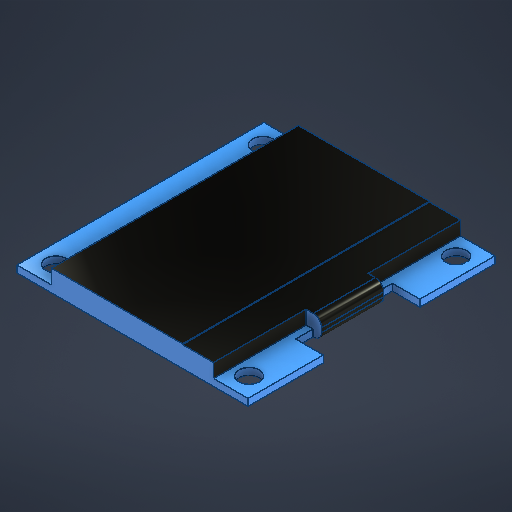
# Autodesk Inventor part: 1.3in OLED
Saved by Autodesk Inventor 2026.2 (Build 302298010, 298A)
## iProperties
Created: 2026-09-25
Part Number: 1.3in OLED
Material: 열가소성 수지
Document SubType Name: Modeling
Designer: work
Density: 1.28 g/cm^3
Appearance: 시안색
Author: work
Autodesk Inventor part; units mm, degrees
ref_plane "YZ Plane" through (0, 0, 0) normal (1, 0, 0) x (0, 1, 0)
ref_plane "XZ Plane" through (0, 0, 0) normal (0, 1, 0) x (-1, 0, 0)
ref_plane "XY Plane" through (0, 0, 0) normal (0, 0, 1) x (1, 0, 0)
sketch "스케치1" plane through (0, 0, 0) normal (0, 1, 0) x (-1, 0, 0)
  line L0 (0, 0) -> (33.5, 0)
  line L1 (33.5, 0) -> (33.5, -35.8)
  line L2 (33.5, -35.8) -> (0, -35.8)
  line L3 (0, -35.8) -> (0, 0)
  line L4 (0, -10.9) -> (4, -10.9)
  line L5 (4, -10.9) -> (4, -24.9)
  line L6 (4, -24.9) -> (0, -24.9)
  line L7 (0, -24.9) -> (0, -10.9)
  line L8 (2.75, -2.9) -> (30.75, -2.9) construction
  line L9 (30.75, -2.9) -> (30.75, -32.9) construction
  line L10 (30.75, -32.9) -> (2.75, -32.9) construction
  line L11 (2.75, -32.9) -> (2.75, -2.9) construction
  circle A0 centre (2.75, -2.9) radius 1.5
  circle A1 centre (30.75, -2.9) radius 1.5
  circle A2 centre (30.75, -32.9) radius 1.5
  circle A3 centre (2.75, -32.9) radius 1.5
  point P0 (0, -17.9)
  point P1 (16.75, -32.9)
  point P2 (16.75, -35.8)
  point P3 (33.5, -17.9)
  point P4 (30.75, -17.9)
  dimension "d0" = 33.5
  dimension "d1" = 35.8
  dimension "d2" = 4
  dimension "d3" = 14
  dimension "d4" = 28
  dimension "d5" = 30
  dimension "d6" = 3
  dimension "d7" = 3
  dimension "d8" = 3
  dimension "d9" = 3
  constraints: 24 end point, 6 midpoint, 6 parallel, 4 centre point, 4 coincident, 3 horizontal, 3 perpendicular, 1 horizontal alignment, 1 vertical alignment
  measures "d0" distance of L1.end L2.end
  measures "d1" distance of L0.end L1.end
  measures "d2" distance of L5.end L6.end
  measures "d3" distance of L4.end L5.end
  measures "d4" distance of L9.end L10.end
  measures "d5" distance of L8.end L9.end
  measures "d6" diameter of A0
  measures "d7" diameter of A1
  measures "d8" diameter of A2
  measures "d9" diameter of A3
extrude "돌출1" add sketch "스케치1" along normal blind 1 contours L0 L1 L2 L3 L6 L5 L4
sketch "스케치2" plane through (0, 1, 0) normal (0, 1, 0) x (1, 0, 0)
  line L0 (-28.5, 35.8) -> (-5, 35.8)
  line L1 (-5, 35.8) -> (-5, 0)
  line L2 (-5, 0) -> (-28.5, 0)
  line L3 (-28.5, 0) -> (-28.5, 35.8)
  line L4 (0, 35.8) -> (-33.5, 35.8) projected
  line L5 (0, 24.9) -> (0, 35.8) projected
  line L6 (-33.5, 35.8) -> (-33.5, 0) projected
  line L7 (-5, 22.4) -> (-2.736, 22.4)
  line L8 (-2.736, 22.4) -> (-2.736, 13.4)
  line L9 (-2.736, 13.4) -> (-5, 13.4)
  line L10 (-5, 13.4) -> (-5, 22.4)
  point P0 (0, 0)
  point P1 (-5, 17.9)
  dimension "d12" = 5
  dimension "d13" = 5
  dimension "d14" = 9
  constraints: 16 end point, 4 parallel, 2 horizontal, 2 midpoint, 2 perpendicular, 2 point on line
  measures "d12" distance between parallel lines of L5 L1
  measures "d13" distance between parallel lines of L6 L3
  measures "d14" distance of L7.end L8.end
extrude "돌출2" add sketch "스케치2" along normal blind 2
extrude "돌출3" add sketch "스케치2" against normal up to surface (1 mm away) contours L7 L8 L9 L1
fillet "모깎기1" radius 1.2 1 edges at (-2.736, 3, -17.9)
sketch "스케치3" plane through (0, 3, 0) normal (0, 1, 0) x (1, 0, 0)
  line L0 (-33.5, 0) -> (-28.5, 0) projected
  line L1 (0, 35.8) -> (-33.5, 35.8) projected
  line L2 (-28.5, 0) -> (-9.5, 0)
  line L3 (-9.5, 0) -> (-9.5, 35.8)
  line L4 (-9.5, 35.8) -> (-28.5, 35.8)
  line L5 (-28.5, 35.8) -> (-28.5, 0)
  point P0 (0, 0)
  dimension "d20" = 19
  constraints: 8 end point, 2 parallel, 1 horizontal, 1 perpendicular, 1 point on line
  measures "d20" distance of L4.end L3.end
extrude "돌출4" add sketch "스케치3" along normal blind 0.1
